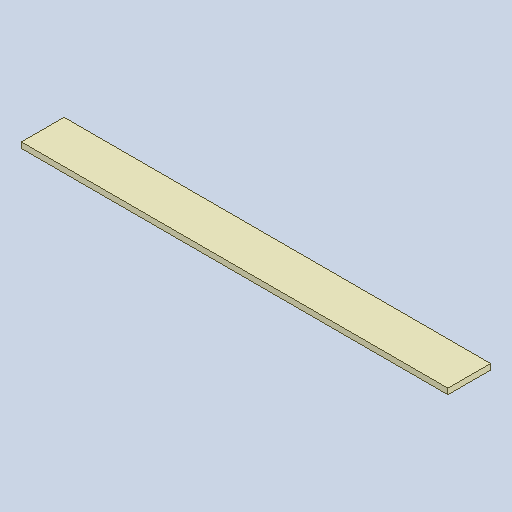
# Autodesk Inventor part: RDS-1503 Mixer Blade
Saved by Autodesk Inventor 2026.2 (Build 302298000, 298)
## iProperties
Created: 2026-10-18
Part Number: RDS-1503 Mixer Blade
Material: Polypropylene
Description: Mixer blade PP, rough
Document SubType Name: Modeling
Designer: admin
Stock Number: Лопасть мешалки ПП (3D-печать), черновик
Density: 0.899 g/cm^3
Appearance: Smooth - Ash
Author: admin
Autodesk Inventor part; units mm, degrees
ref_plane "YZ Plane" through (0, 0, 0) normal (1, 0, 0) x (0, 1, 0)
ref_plane "XZ Plane" through (0, 0, 0) normal (0, 1, 0) x (-1, 0, 0)
ref_plane "XY Plane" through (0, 0, 0) normal (0, 0, 1) x (1, 0, 0)
sketch "Sketch1" plane through (0, 0, 0) normal (0, 1, 0) x (-1, 0, 0)
  line L0 (300, -30) -> (-300, -30)
  line L1 (-300, -30) -> (-300, 30)
  line L2 (-300, 30) -> (300, 30)
  line L3 (300, 30) -> (300, -30)
  constraints: 8 end point, 2 parallel, 1 horizontal, 1 perpendicular
extrude "Extrusion1" add sketch "Sketch1" along normal blind 8
equation "\"d0\" = Height"
equation "\"Height\" = 8"
body "Solid1"
